Autodesk Inventor part; units mm, degrees
(part 2 of 2)
  arc A375 (2.7821, 10.2076) -> (2.7255, 10.1776) centre (2.7718, 10.1587) ccw
  arc A376 (3.3578, 10.033) -> (2.7821, 10.2076) centre (0, 0) ccw
  arc A377 (3.3882, 9.9766) -> (3.3578, 10.033) centre (3.3392, 9.9866) ccw
  arc A378 (3.3882, 9.9766) -> (3.3546, 9.711) centre (4.4537, 9.707) ccw
  arc A379 (3.3546, 9.711) -> (4.4946, 9.2388) centre (4.0143, 9.6915) ccw
  arc A380 (4.4946, 9.2388) -> (4.721, 9.5714) centre (3.7146, 10.0132) ccw
  arc A381 (4.7201, 9.4687) -> (4.6587, 9.4503) centre (4.7004, 9.4228) ccw
  arc A382 (5.2506, 9.1852) -> (4.7201, 9.4687) centre (0, 0) ccw
  arc A383 (5.2694, 9.1239) -> (5.2506, 9.1852) centre (5.2233, 9.1433) ccw
  arc A384 (5.3354, 9.243) -> (5.1847, 8.87) centre (6.2619, 8.6516) ccw
  arc A385 (5.1847, 8.87) -> (6.2107, 8.1844) centre (5.8279, 8.7221) ccw
  arc A386 (3.4297, 10.1062) -> (3.3546, 9.711) centre (4.4537, 9.707) ccw
  arc A387 (2.6059, 9.9381) -> (2.763, 10.3085) centre (1.6898, 10.5455) ccw
  arc A388 (1.3922, 10.5812) -> (1.3957, 10.1789) centre (2.4744, 10.3894) ccw
  arc A389 (0.617, 10.2556) -> (0.6989, 10.6494) centre (-0.4, 10.6725) ccw
  arc A390 (-0.6989, 10.6494) -> (-0.617, 10.2556) centre (0.4, 10.6725) ccw
  arc A391 (-1.3957, 10.1789) -> (-1.3922, 10.5812) centre (-2.4744, 10.3894) ccw
  arc A392 (-2.763, 10.3085) -> (-2.6059, 9.9381) centre (-1.6898, 10.5455) ccw
  arc A393 (-3.3546, 9.711) -> (-3.4297, 10.1062) centre (-4.4537, 9.707) ccw
  arc A394 (-4.721, 9.5714) -> (-4.4946, 9.2388) centre (-3.7146, 10.0132) ccw
  arc A395 (-5.1847, 8.87) -> (-5.3354, 9.243) centre (-6.2619, 8.6516) ccw
  arc A396 (-6.4976, 8.4664) -> (-6.2107, 8.1844) centre (-5.5967, 9.0961) ccw
  arc A397 (-6.8155, 7.688) -> (-7.0361, 8.0245) centre (-7.8294, 7.2638) ccw
  arc A398 (-8.0245, 7.0361) -> (-7.688, 6.8155) centre (-7.2638, 7.8294) ccw
  arc A399 (-8.1844, 6.2107) -> (-8.4664, 6.4976) centre (-9.0961, 5.5967) ccw
  arc A400 (-9.243, 5.3354) -> (-8.87, 5.1847) centre (-8.6516, 6.2619) ccw
  arc A401 (-9.2388, 4.4946) -> (-9.5714, 4.721) centre (-10.0132, 3.7146) ccw
  arc A402 (-10.1062, 3.4297) -> (-9.711, 3.3546) centre (-9.707, 4.4537) ccw
  arc A403 (-9.9381, 2.6059) -> (-10.3085, 2.763) centre (-10.5455, 1.6898) ccw
  arc A404 (-10.5812, 1.3922) -> (-10.1789, 1.3957) centre (-10.3894, 2.4744) ccw
  arc A405 (-10.2556, 0.617) -> (-10.6494, 0.6989) centre (-10.6725, -0.4) ccw
  arc A406 (-10.6494, -0.6989) -> (-10.2556, -0.617) centre (-10.6725, 0.4) ccw
  arc A407 (-10.1789, -1.3957) -> (-10.5812, -1.3922) centre (-10.3894, -2.4744) ccw
  arc A408 (-10.3085, -2.763) -> (-9.9381, -2.6059) centre (-10.5455, -1.6898) ccw
  arc A409 (-9.711, -3.3546) -> (-10.1062, -3.4297) centre (-9.707, -4.4537) ccw
  arc A410 (-9.5714, -4.721) -> (-9.2388, -4.4946) centre (-10.0132, -3.7146) ccw
  arc A411 (-8.87, -5.1847) -> (-9.243, -5.3354) centre (-8.6516, -6.2619) ccw
  arc A412 (-8.4664, -6.4976) -> (-8.1844, -6.2107) centre (-9.0961, -5.5967) ccw
  arc A413 (-7.688, -6.8155) -> (-8.0245, -7.0361) centre (-7.2638, -7.8294) ccw
  arc A414 (-7.0361, -8.0245) -> (-6.8155, -7.688) centre (-7.8294, -7.2638) ccw
  arc A415 (-6.2107, -8.1844) -> (-6.4976, -8.4664) centre (-5.5967, -9.0961) ccw
  arc A416 (-5.3354, -9.243) -> (-5.1847, -8.87) centre (-6.2619, -8.6516) ccw
  arc A417 (-4.4946, -9.2388) -> (-4.721, -9.5714) centre (-3.7146, -10.0132) ccw
  arc A418 (-3.4297, -10.1062) -> (-3.3546, -9.711) centre (-4.4537, -9.707) ccw
  arc A419 (-2.6059, -9.9381) -> (-2.763, -10.3085) centre (-1.6898, -10.5455) ccw
  arc A420 (-1.3922, -10.5812) -> (-1.3957, -10.1789) centre (-2.4744, -10.3894) ccw
  arc A421 (-0.617, -10.2556) -> (-0.6989, -10.6494) centre (0.4, -10.6725) ccw
  arc A422 (0.6989, -10.6494) -> (0.617, -10.2556) centre (-0.4, -10.6725) ccw
  arc A423 (1.3957, -10.1789) -> (1.3922, -10.5812) centre (2.4744, -10.3894) ccw
  arc A424 (2.763, -10.3085) -> (2.6059, -9.9381) centre (1.6898, -10.5455) ccw
  arc A425 (3.3546, -9.711) -> (3.4297, -10.1062) centre (4.4537, -9.707) ccw
  arc A426 (4.721, -9.5714) -> (4.4946, -9.2388) centre (3.7146, -10.0132) ccw
  arc A427 (5.1847, -8.87) -> (5.3354, -9.243) centre (6.2619, -8.6516) ccw
  arc A428 (6.4976, -8.4664) -> (6.2107, -8.1844) centre (5.5967, -9.0961) ccw
  arc A429 (6.8155, -7.688) -> (7.0361, -8.0245) centre (7.8294, -7.2638) ccw
  arc A430 (8.0245, -7.0361) -> (7.688, -6.8155) centre (7.2638, -7.8294) ccw
  arc A431 (8.1844, -6.2107) -> (8.4664, -6.4976) centre (9.0961, -5.5967) ccw
  arc A432 (9.243, -5.3354) -> (8.87, -5.1847) centre (8.6516, -6.2619) ccw
  arc A433 (9.2388, -4.4946) -> (9.5714, -4.721) centre (10.0132, -3.7146) ccw
  arc A434 (10.1062, -3.4297) -> (9.711, -3.3546) centre (9.707, -4.4537) ccw
  arc A435 (9.9381, -2.6059) -> (10.3085, -2.763) centre (10.5455, -1.6898) ccw
  arc A436 (10.5812, -1.3922) -> (10.1789, -1.3957) centre (10.3894, -2.4744) ccw
  arc A437 (10.2556, -0.617) -> (10.6494, -0.6989) centre (10.6725, 0.4) ccw
  arc A438 (10.6494, 0.6989) -> (10.2556, 0.617) centre (10.6725, -0.4) ccw
  arc A439 (10.1789, 1.3957) -> (10.5812, 1.3922) centre (10.3894, 2.4744) ccw
  arc A440 (10.3085, 2.763) -> (9.9381, 2.6059) centre (10.5455, 1.6898) ccw
  arc A441 (9.711, 3.3546) -> (10.1062, 3.4297) centre (9.707, 4.4537) ccw
  arc A442 (9.5714, 4.721) -> (9.2388, 4.4946) centre (10.0132, 3.7146) ccw
  arc A443 (8.87, 5.1847) -> (9.243, 5.3354) centre (8.6516, 6.2619) ccw
  arc A444 (8.4664, 6.4976) -> (8.1844, 6.2107) centre (9.0961, 5.5967) ccw
  arc A445 (7.688, 6.8155) -> (8.0245, 7.0361) centre (7.2638, 7.8294) ccw
  arc A446 (7.0361, 8.0245) -> (6.8155, 7.688) centre (7.8294, 7.2638) ccw
  arc A447 (6.2107, 8.1844) -> (6.4976, 8.4664) centre (5.5967, 9.0961) ccw
  point P0 (3.3882, 9.9766)
  point P1 (2.7255, 10.1776)
  point P2 (1.3768, 10.4459)
  point P3 (0.6876, 10.5137)
  point P4 (-0.6876, 10.5137)
  point P5 (-1.3768, 10.4459)
  point P6 (-2.7255, 10.1776)
  point P7 (-3.3882, 9.9766)
  point P8 (-4.6587, 9.4503)
  point P9 (-5.2694, 9.1239)
  point P10 (-6.4128, 8.3599)
  point P11 (-6.9481, 7.9205)
  point P12 (-7.9205, 6.9481)
  point P13 (-8.3599, 6.4128)
  point P14 (-9.4503, 4.6587)
  point P15 (-9.9766, 3.3882)
  point P16 (-10.1776, 2.7255)
  point P17 (-10.4459, 1.3768)
  point P18 (-10.5137, 0.6876)
  point P19 (-10.5137, -0.6876)
  point P20 (-10.4459, -1.3768)
  point P21 (-10.1776, -2.7255)
  point P22 (-9.9766, -3.3882)
  point P23 (-9.4503, -4.6587)
  point P24 (-9.1239, -5.2694)
  point P25 (-8.3599, -6.4128)
  point P26 (-7.9205, -6.9481)
  point P27 (-6.9481, -7.9205)
  point P28 (-6.4128, -8.3599)
  point P29 (-5.2694, -9.1239)
  point P30 (-4.6587, -9.4503)
  point P31 (-3.3882, -9.9766)
  point P32 (-2.7255, -10.1776)
  point P33 (-1.3768, -10.4459)
  point P34 (-0.6876, -10.5137)
  point P35 (0.6876, -10.5137)
  point P36 (1.3768, -10.4459)
  point P37 (2.7255, -10.1776)
  point P38 (3.3882, -9.9766)
  point P39 (4.6587, -9.4503)
  point P40 (5.2694, -9.1239)
  point P41 (6.4128, -8.3599)
  point P42 (6.9481, -7.9205)
  point P43 (7.9205, -6.9481)
  point P44 (8.3599, -6.4128)
  point P45 (9.1239, -5.2694)
  point P46 (9.4503, -4.6587)
  point P47 (9.9766, -3.3882)
  point P48 (10.1776, -2.7255)
  point P49 (10.4459, -1.3768)
  point P50 (10.5137, -0.6876)
  point P51 (10.5137, 0.6876)
  point P52 (10.4459, 1.3768)
  point P53 (10.1776, 2.7255)
  point P54 (9.9766, 3.3882)
  point P55 (9.4503, 4.6587)
  point P56 (9.1239, 5.2694)
  point P57 (8.3599, 6.4128)
  point P58 (7.9205, 6.9481)
  point P59 (6.9481, 7.9205)
  point P60 (6.4128, 8.3599)
  point P61 (1.3922, 10.5812)
  point P62 (1.3768, 10.4459)
  point P63 (2.7255, 10.1776)
  dimension "d21" = 0.1
  dimension "d24" = 360
  constraints: 574 point on circle, 254 centre point, 508 other
  measures "d21" radial gap between concentric circles of A169 A385
extrude "Extrusion3" cut sketch "Skizze4" along normal up to surface (6 mm away) contours A388 A183 A182 A181 A180 A179 A387 A374 A373 A372
pattern_circular "Runde Anordnung1" count 32 over 360 about axis through (0, 0, -10) along (0, 0, 1) of "Extrusion3"
equation "\"d10\" = d8"
